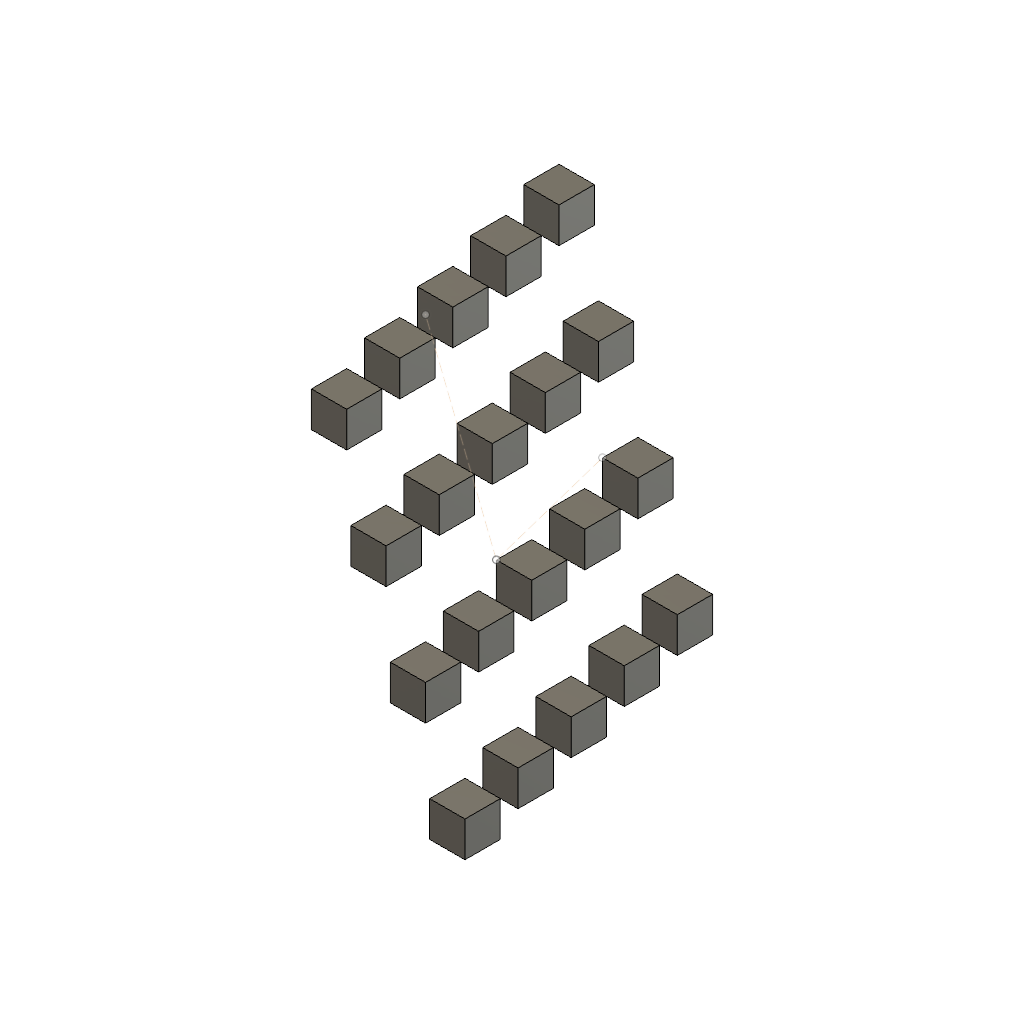
oblique_axes (Autodesk Fusion 360 design; units mm, degrees)
part number: 2026-10-20-22-13-26-644
Autodesk Fusion 360 part; units mm, degrees
sketch "Sketch1" plane through (0, 0, 0) normal (0, 0, 1) x (1, 0, 0)
  line L0 (10, 0) -> (20, 0)
  line L1 (20, 0) -> (20, 10)
  line L2 (20, 10) -> (10, 10)
  line L3 (10, 10) -> (10, 0)
extrude "SeedFeature0" add sketch "Sketch1" along normal blind 10 makes body 1
sketch "ObliquePatternDirections" plane through (0, 0, 0) normal (0, 0, 1) x (1, 0, 0)
  line L0 (0, 0) -> (30, 40) construction
  line L1 (0, 0) -> (-20, 50) construction
pattern_linear "ProbeRectangularSymmetryHoldout" count 5 spacing 25 along (0.6, 0.8, 0) both ways count 4 spacing 30 along (-0.371391, 0.928477, 0) both ways of bodies 1 makes body 2 at (-8.8583, -61.1876, 3.3333) makes body 3 at (6.1417, -41.1876, 3.3333) makes body 4 at (21.1417, -21.1876, 3.3333) makes body 5 at (36.1417, -1.1876, 3.3333) makes body 6 at (51.1417, 18.8124, 3.3333) makes body 7 at (-20, -33.3333, 3.3333) makes body 8 at (-5, -13.3333, 3.3333) makes body 9 at (25, 26.6667, 3.3333) makes body 10 at (40, 46.6667, 3.3333) makes body 11 at (-31.1417, -5.479, 3.3333) makes body 12 at (-16.1417, 14.521, 3.3333) makes body 13 at (-1.1417, 34.521, 3.3333) makes body 14 at (13.8583, 54.521, 3.3333) makes body 15 at (28.8583, 74.521, 3.3333) makes body 16 at (-42.2834, 22.3753, 3.3333) makes body 17 at (-27.2834, 42.3753, 3.3333) makes body 18 at (-12.2834, 62.3753, 3.3333) makes body 19 at (2.7166, 82.3753, 3.3333) makes body 20 at (17.7166, 102.3753, 3.3333)
named bodies: "SeedBody0", "SeedBody0 (1)", "SeedBody0 (2)", "SeedBody0 (3)", "SeedBody0 (4)", "SeedBody0 (5)", "SeedBody0 (6)", "SeedBody0 (7)", "SeedBody0 (8)", "SeedBody0 (9)", "SeedBody0 (10)", "SeedBody0 (11)", "SeedBody0 (12)", "SeedBody0 (13)", "SeedBody0 (14)", "SeedBody0 (15)", "SeedBody0 (16)", "SeedBody0 (17)", "SeedBody0 (18)", "SeedBody0 (19)"
